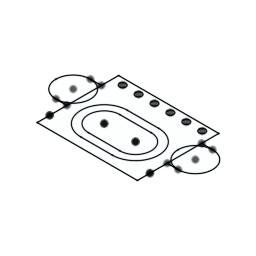
VL53 (Autodesk Fusion 360 design; units mm, degrees)
part number: 2026-07-28-17-20-25-282
Autodesk Fusion 360 part; units mm, degrees
sketch "Sketch1" plane through (0, 0, 369.6) normal (0, 0, 1) x (-1, 0, 0)
  line L0 (-8, 3.2) -> (-8, 5.2)
  line L1 (-8, 5.2) -> (8, 5.2)
  line L2 (8, 3.2) -> (8, -7.8)
  line L3 (8, 5.2) -> (8, 3.2)
  circle A0 centre (9.75, -2.3) radius 2.75
  line L4 (9.75, 0.45) -> (8, 0.45)
  line L5 (8, -7.8) -> (-8, -7.8)
  line L6 (-8, -7.8) -> (-8, 3.2)
  circle A1 centre (-9.75, -2.3) radius 2.75
  line L7 (-9.75, -5.05) -> (-8, -5.05)
  line L8 (-9.75, 0.45) -> (-8, 0.45)
  line L9 (9.75, -5.05) -> (8, -5.05)
  circle A2 centre (-6.35, -6.8) radius 0.5
  circle A3 centre (-3.81, -6.8) radius 0.5
  circle A4 centre (-1.27, -6.8) radius 0.5
  circle A5 centre (1.27, -6.8) radius 0.5
  circle A6 centre (3.81, -6.8) radius 0.5
  circle A7 centre (6.35, -6.8) radius 0.5
  line L10 (2.5, 3.7) -> (-2.5, 3.7)
  arc A8 (2.5, -3.7) -> (2.5, 3.7) centre (2.5, 0) ccw
  line L11 (2.5, -3.7) -> (-2.5, -3.7)
  arc A9 (-2.5, 3.7) -> (-2.5, -3.7) centre (-2.5, 0) ccw
  arc A10 (-2.5, 2.5) -> (-2.5, -2.5) centre (-2.5, 0) ccw
  line L12 (2.5, 2.5) -> (-2.5, 2.5)
  arc A11 (2.5, -2.5) -> (2.5, 2.5) centre (2.5, 0) ccw
  line L13 (2.5, -2.5) -> (-2.5, -2.5)
extrude "Extrude1" add sketch "Sketch1" along normal blind 2 contours L0 L1 L2 L3 A0 L5 L6 A1 | L6 A1 L8 | L6 A1 | L6 A1 | L6 A1 L7 | L2 A0 | L2 A0 | L2 A0 L9 | L10 A8 L11 A9 | A10 L12 A11 L13 makes body 1
extrude "Extrude2" add sketch "Sketch1" along normal blind 3 separate body contours L10 A8 L11 A9 | A10 L12 A11 L13 makes body 2
extrude "Extrude3" add sketch "Sketch1" along normal blind 4 separate body contours A10 L12 A11 L13 makes body 3
